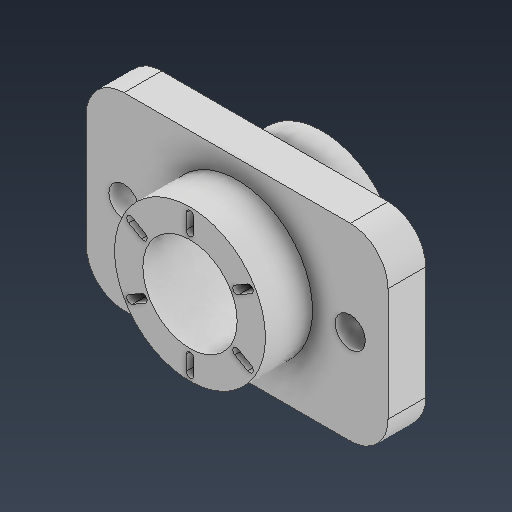
# Autodesk Inventor part: Worksheet3
Saved by Autodesk Inventor 2026.4 (Build 304435000, 435)
## iProperties
Created: 2026-08-13
Part Number: Worksheet3
Material: Generic
Document SubType Name: Modeling
Designer: YmCris
Density: 1 g/cm^3
Appearance: Default
Author: YmCris
Autodesk Inventor part; units mm, degrees
ref_plane "YZ Plane" through (0, 0, 0) normal (1, 0, 0) x (0, 1, 0)
ref_plane "XZ Plane" through (0, 0, 0) normal (0, 1, 0) x (-1, 0, 0)
ref_plane "XY Plane" through (0, 0, 0) normal (0, 0, 1) x (1, 0, 0)
sketch "Sketch1" plane through (0, 0, 0) normal (0, 0, 1) x (1, 0, 0)
  line L0 (30, -25) -> (-30, -25)
  line L1 (-30, 25) -> (30, 25)
  line L2 (-30, -25) -> (30, -25)
  line L3 (40, -15) -> (40, 15)
  line L4 (30, 25) -> (-30, 25)
  line L5 (-40, 15) -> (-40, -15)
  arc A0 (40, 15) -> (30, 25) centre (30, 15) ccw
  arc A1 (-30, 25) -> (-40, 15) centre (-30, 15) ccw
  arc A2 (30, -25) -> (40, -15) centre (30, -15) ccw
  arc A3 (-40, -15) -> (-30, -25) centre (-30, -15) ccw
  constraints: 12 end point, 8 point on circle, 4 centre point, 3 parallel, 2 horizontal, 2 tangent, 1 perpendicular
extrude "Extrusion1" add sketch "Sketch1" along normal blind 10
sketch "Sketch2" plane through (0, 0, 0) normal (0, 0, -1) x (-1, 0, 0)
  circle A0 centre (0, 0) radius 20
  dimension "d7" = 40
  constraints: 1 centre point, 1 coincident
  measures "d7" diameter of A0
extrude "Extrusion2" add sketch "Sketch2" along normal blind 12.5
sketch "Sketch3" plane through (0, 0, 10) normal (0, 0, 1) x (1, 0, 0)
  circle A0 centre (0, 0) radius 20
  dimension "d10" = 40
  constraints: 1 centre point, 1 coincident
  measures "d10" diameter of A0
extrude "Extrusion3" add sketch "Sketch3" along normal blind 12.5
sketch "Sketch4" plane through (0, 0, 22.5) normal (0, 0, 1) x (1, 0, 0)
  circle A0 centre (0, 0) radius 12.5
  dimension "d13" = 25
  constraints: 1 centre point, 1 coincident
  measures "d13" diameter of A0
extrude "Extrusion4" cut sketch "Sketch4" against normal blind 35
sketch "Sketch5" plane through (0, 0, 22.5) normal (0, 0, 1) x (1, 0, 0)
  line L0 (-1, 18.2359) -> (-1, 14.2359)
  line L1 (1, 14.2359) -> (1, 18.2359)
  arc A0 (1, 18.2039) -> (-1, 18.2039) centre (0, 18.2359) ccw
  arc A1 (-1, 14.2679) -> (1, 14.2679) centre (0, 14.2359) ccw
  line L2 (-16.2928, 8.2519) -> (-12.8287, 6.2519)
  line L3 (-11.8287, 7.984) -> (-15.2928, 9.984)
  arc A2 (-15.2651, 9.968) -> (-16.2651, 8.2359) centre (-15.7928, 9.118) ccw
  arc A3 (-12.8563, 6.2679) -> (-11.8563, 8) centre (-12.3287, 7.118) ccw
  line L4 (-15.2928, -9.984) -> (-11.8287, -7.984)
  line L5 (-12.8287, -6.2519) -> (-16.2928, -8.2519)
  arc A4 (-16.2651, -8.2359) -> (-15.2651, -9.968) centre (-15.7928, -9.118) ccw
  arc A5 (-11.8563, -8) -> (-12.8563, -6.2679) centre (-12.3287, -7.118) ccw
  line L6 (1, -18.2359) -> (1, -14.2359)
  line L7 (-1, -14.2359) -> (-1, -18.2359)
  arc A6 (-1, -18.2039) -> (1, -18.2039) centre (0, -18.2359) ccw
  arc A7 (1, -14.2679) -> (-1, -14.2679) centre (0, -14.2359) ccw
  line L8 (16.2928, -8.2519) -> (12.8287, -6.2519)
  line L9 (11.8287, -7.984) -> (15.2928, -9.984)
  arc A8 (15.2651, -9.968) -> (16.2651, -8.2359) centre (15.7928, -9.118) ccw
  arc A9 (12.8563, -6.2679) -> (11.8563, -8) centre (12.3287, -7.118) ccw
  line L10 (15.2928, 9.984) -> (11.8287, 7.984)
  line L11 (12.8287, 6.2519) -> (16.2928, 8.2519)
  arc A10 (16.2651, 8.2359) -> (15.2651, 9.968) centre (15.7928, 9.118) ccw
  arc A11 (11.8563, 8) -> (12.8563, 6.2679) centre (12.3287, 7.118) ccw
  point P0 (0, 0)
  point P1 (-12.8563, 6.2679)
  point P2 (-11.8563, 8)
  point P3 (11.8563, 8)
  point P4 (12.8563, 6.2679)
  point P5 (11.8563, -8)
  point P6 (-12.8563, -6.2679)
  dimension "d20" = 360
  constraints: 24 end point, 24 point on circle, 12 centre point, 12 point on line, 1 parallel, 85 other
extrude "Extrusion5" cut sketch "Sketch5" against normal blind 35
sketch "Sketch6" plane through (0, 0, 0) normal (0, 0, -1) x (-1, 0, 0)
  circle A0 centre (30, 0) radius 7.5
  line L0 (0, 4.7606) -> (0, -5.3119)
  circle A1 centre (-30, 0) radius 7.5
  point P0 (0, 0)
  dimension "d24" = 15
  constraints: 2 centre point, 2 end point, 1 symmetric about line, 1 vertical, 1 other
  measures "d24" diameter of A0
extrude "Extrusion6" add sketch "Sketch6" along normal blind 5 contours A0
sketch "Sketch7" plane through (0, 0, 0) normal (0, 0, -1) x (-1, 0, 0)
  circle A0 centre (-30, 0) radius 7.5
  point P0 (0, 0)
  dimension "d27" = 15
  constraints: 1 centre point
  measures "d27" diameter of A0
extrude "Extrusion7" add sketch "Sketch7" along normal blind 2
sketch "Sketch8" plane through (30, 0, -2) normal (0, 0, -1) x (-1, 0, 0)
  circle A0 centre (0, 0) radius 4
  point P0 (30, 0)
  dimension "d30" = 8
  constraints: 1 centre point
  measures "d30" diameter of A0
extrude "Extrusion8" cut sketch "Sketch8" against normal blind 37
sketch "Sketch9" plane through (30, 0, -2) normal (0, 0, -1) x (-1, 0, 0)
  circle A0 centre (0, 5.75) radius 1
  circle A1 centre (-5.75, 0) radius 1
  circle A2 centre (0, -5.75) radius 1
  circle A3 centre (5.75, 0) radius 1
  point P0 (30, 0)
  point P1 (0, 0)
  dimension "d36" = 360
  constraints: 4 centre point, 9 other
extrude "Extrusion9" cut sketch "Sketch9" against normal blind 2
sketch "Sketch10" plane through (-30, 0, -5) normal (0, 0, -1) x (-1, 0, 0)
  circle A0 centre (0, 0) radius 4
  point P0 (-30, 0)
  constraints: 1 centre point
extrude "Extrusion10" cut sketch "Sketch10" against normal blind 15
sketch "Sketch11" plane through (-30, 0, -5) normal (0, 0, -1) x (-1, 0, 0)
  circle A0 centre (0, 5.75) radius 1
  circle A1 centre (-5.75, 0) radius 1
  circle A2 centre (0, -5.75) radius 1
  circle A3 centre (5.75, 0) radius 1
  point P0 (-30, 0)
  point P1 (0, 0)
  dimension "d46" = 360
  constraints: 4 centre point, 9 other
extrude "Extrusion11" cut sketch "Sketch11" against normal blind 5
body "Solid1"
